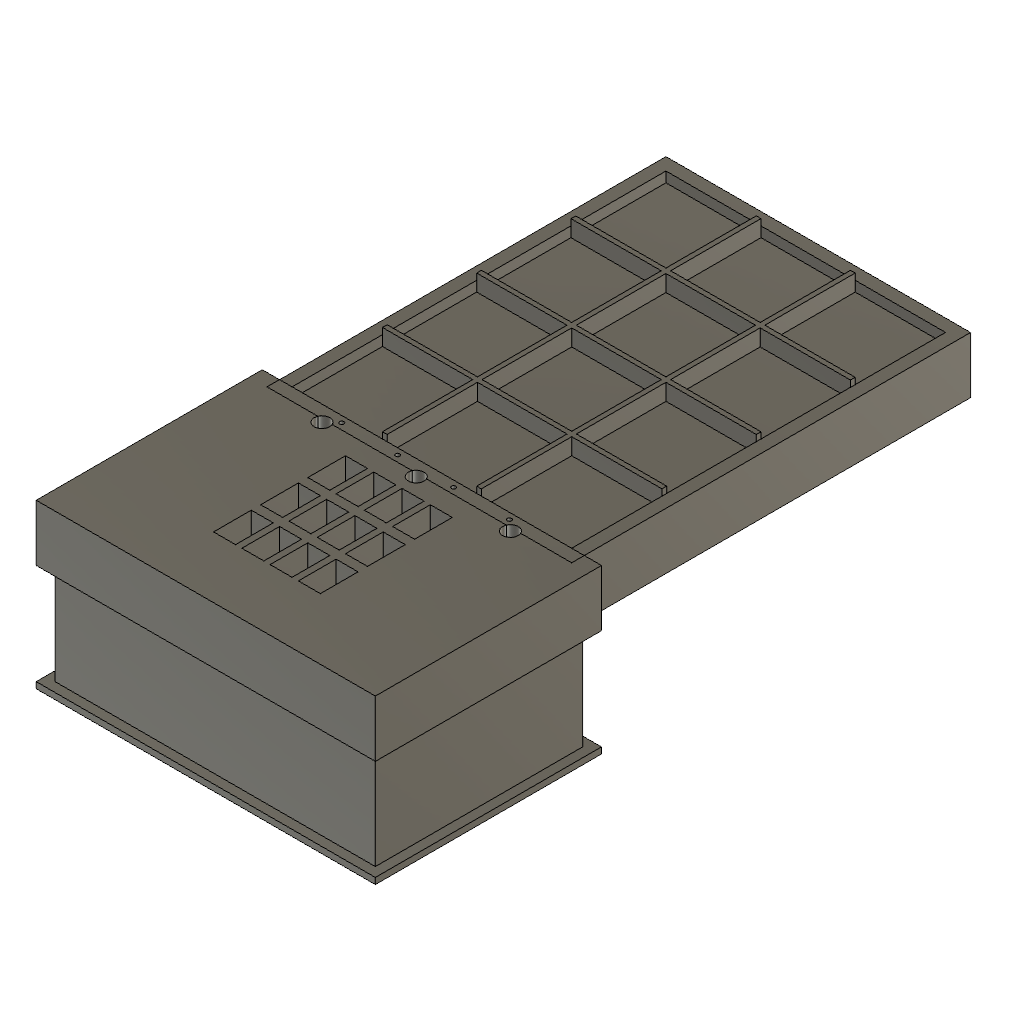
BedPrototype_before (Autodesk Fusion 360 design; units mm, degrees)
part number: 2026-11-06-12-43-00-415
Autodesk Fusion 360 part; units mm, degrees
sketch "BedFrame_CellDeckSketch" plane through (0, 0, 0) normal (0, 0, 1) x (1, 0, 0)
  line L0 (-97, -127) -> (97, -127)
  line L1 (97, -127) -> (97, 127)
  line L2 (97, 127) -> (-97, 127)
  line L3 (-97, 127) -> (-97, -127)
extrude "BedFrame_CellDeckExtrude" add sketch "BedFrame_CellDeckSketch" along normal blind 36 makes body 1
ref_plane "WorkPlane50" through (0, 0, 36) normal (0, 0, 1) x (1, 0, 0)
ref_plane "WorkPlane51" through (0, 0, 28) normal (0, 0, 1) x (1, 0, 0)
ref_plane "WorkPlane52" through (0, 0, 4) normal (0, 0, 1) x (1, 0, 0)
sketch "BedFrame_Well_0_0" plane through (0, 0, 36) normal (0, 0, 1) x (1, 0, 0)
  line L0 (-89, -119) -> (-31, -119)
  line L1 (-31, -119) -> (-31, -61)
  line L2 (-31, -61) -> (-89, -61)
  line L3 (-89, -61) -> (-89, -119)
extrude "BedFrame_WellCut_0_0" cut sketch "BedFrame_Well_0_0" against normal blind 6.5 bodies 1
sketch "Sketch1205" plane through (0, 0, 28) normal (0, 0, 1) x (1, 0, 0)
  circle A0 centre (-60, -90) radius 3.25
extrude "BedFrame_Port_0_0" cut sketch "Sketch1205" against normal blind 4 bodies 1
sketch "Sketch1206" plane through (0, 0, 28) normal (0, 0, 1) x (1, 0, 0)
  circle A0 centre (-60, -90) radius 5
extrude "BedFrame_Stem_0_0" cut sketch "Sketch1206" against normal blind 14 bodies 1
sketch "BedFrame_Run_0_0" plane through (0, 0, 4) normal (0, 0, 1) x (1, 0, 0)
  line L0 (-65, -119) -> (-55, -119)
  line L1 (-55, -119) -> (-55, -90)
  line L2 (-55, -90) -> (-65, -90)
  line L3 (-65, -90) -> (-65, -119)
extrude "BedFrame_RunCut_0_0" cut sketch "BedFrame_Run_0_0" against normal blind 12 bodies 1
sketch "BedFrame_Clip_0_0_1" plane through (0, 0, 4) normal (0, 0, 1) x (1, 0, 0)
  line L0 (-72, -101.6667) -> (-60, -101.6667)
  line L1 (-60, -101.6667) -> (-60, -97.6667)
  line L2 (-60, -97.6667) -> (-72, -97.6667)
  line L3 (-72, -97.6667) -> (-72, -101.6667)
extrude "BedFrame_ClipSlot_0_0_1" cut sketch "BedFrame_Clip_0_0_1" against normal blind 13 bodies 1
sketch "BedFrame_Clip_0_0_2" plane through (0, 0, 4) normal (0, 0, 1) x (1, 0, 0)
  line L0 (-72, -111.3333) -> (-60, -111.3333)
  line L1 (-60, -111.3333) -> (-60, -107.3333)
  line L2 (-60, -107.3333) -> (-72, -107.3333)
  line L3 (-72, -107.3333) -> (-72, -111.3333)
extrude "BedFrame_ClipSlot_0_0_2" cut sketch "BedFrame_Clip_0_0_2" against normal blind 13 bodies 1
sketch "BedFrame_Well_0_1" plane through (0, 0, 36) normal (0, 0, 1) x (1, 0, 0)
  line L0 (-89, -59) -> (-31, -59)
  line L1 (-31, -59) -> (-31, -1)
  line L2 (-31, -1) -> (-89, -1)
  line L3 (-89, -1) -> (-89, -59)
extrude "BedFrame_WellCut_0_1" cut sketch "BedFrame_Well_0_1" against normal blind 6.5 bodies 1
sketch "Sketch1211" plane through (0, 0, 28) normal (0, 0, 1) x (1, 0, 0)
  circle A0 centre (-60, -30) radius 3.25
extrude "BedFrame_Port_0_1" cut sketch "Sketch1211" against normal blind 4 bodies 1
sketch "Sketch1212" plane through (0, 0, 28) normal (0, 0, 1) x (1, 0, 0)
  circle A0 centre (-60, -30) radius 5
extrude "BedFrame_Stem_0_1" cut sketch "Sketch1212" against normal blind 14 bodies 1
sketch "BedFrame_Run_0_1" plane through (0, 0, 4) normal (0, 0, 1) x (1, 0, 0)
  line L0 (-65, -119) -> (-55, -119)
  line L1 (-55, -119) -> (-55, -30)
  line L2 (-55, -30) -> (-65, -30)
  line L3 (-65, -30) -> (-65, -119)
extrude "BedFrame_RunCut_0_1" cut sketch "BedFrame_Run_0_1" against normal blind 12 bodies 1
sketch "BedFrame_Clip_0_1_1" plane through (0, 0, 4) normal (0, 0, 1) x (1, 0, 0)
  line L0 (-72, -61.6667) -> (-60, -61.6667)
  line L1 (-60, -61.6667) -> (-60, -57.6667)
  line L2 (-60, -57.6667) -> (-72, -57.6667)
  line L3 (-72, -57.6667) -> (-72, -61.6667)
extrude "BedFrame_ClipSlot_0_1_1" cut sketch "BedFrame_Clip_0_1_1" against normal blind 13 bodies 1
sketch "BedFrame_Clip_0_1_2" plane through (0, 0, 4) normal (0, 0, 1) x (1, 0, 0)
  line L0 (-72, -91.3333) -> (-60, -91.3333)
  line L1 (-60, -91.3333) -> (-60, -87.3333)
  line L2 (-60, -87.3333) -> (-72, -87.3333)
  line L3 (-72, -87.3333) -> (-72, -91.3333)
extrude "BedFrame_ClipSlot_0_1_2" cut sketch "BedFrame_Clip_0_1_2" against normal blind 13 bodies 1
sketch "BedFrame_Well_0_2" plane through (0, 0, 36) normal (0, 0, 1) x (1, 0, 0)
  line L0 (-89, 1) -> (-31, 1)
  line L1 (-31, 1) -> (-31, 59)
  line L2 (-31, 59) -> (-89, 59)
  line L3 (-89, 59) -> (-89, 1)
extrude "BedFrame_WellCut_0_2" cut sketch "BedFrame_Well_0_2" against normal blind 6.5 bodies 1
sketch "Sketch1217" plane through (0, 0, 28) normal (0, 0, 1) x (1, 0, 0)
  circle A0 centre (-60, 30) radius 3.25
extrude "BedFrame_Port_0_2" cut sketch "Sketch1217" against normal blind 4 bodies 1
sketch "Sketch1218" plane through (0, 0, 28) normal (0, 0, 1) x (1, 0, 0)
  circle A0 centre (-60, 30) radius 5
extrude "BedFrame_Stem_0_2" cut sketch "Sketch1218" against normal blind 14 bodies 1
sketch "BedFrame_Run_0_2" plane through (0, 0, 4) normal (0, 0, 1) x (1, 0, 0)
  line L0 (-65, -119) -> (-55, -119)
  line L1 (-55, -119) -> (-55, 30)
  line L2 (-55, 30) -> (-65, 30)
  line L3 (-65, 30) -> (-65, -119)
extrude "BedFrame_RunCut_0_2" cut sketch "BedFrame_Run_0_2" against normal blind 12 bodies 1
sketch "BedFrame_Clip_0_2_1" plane through (0, 0, 4) normal (0, 0, 1) x (1, 0, 0)
  line L0 (-72, -21.6667) -> (-60, -21.6667)
  line L1 (-60, -21.6667) -> (-60, -17.6667)
  line L2 (-60, -17.6667) -> (-72, -17.6667)
  line L3 (-72, -17.6667) -> (-72, -21.6667)
extrude "BedFrame_ClipSlot_0_2_1" cut sketch "BedFrame_Clip_0_2_1" against normal blind 13 bodies 1
sketch "BedFrame_Clip_0_2_2" plane through (0, 0, 4) normal (0, 0, 1) x (1, 0, 0)
  line L0 (-72, -71.3333) -> (-60, -71.3333)
  line L1 (-60, -71.3333) -> (-60, -67.3333)
  line L2 (-60, -67.3333) -> (-72, -67.3333)
  line L3 (-72, -67.3333) -> (-72, -71.3333)
extrude "BedFrame_ClipSlot_0_2_2" cut sketch "BedFrame_Clip_0_2_2" against normal blind 13 bodies 1
sketch "BedFrame_Well_0_3" plane through (0, 0, 36) normal (0, 0, 1) x (1, 0, 0)
  line L0 (-89, 61) -> (-31, 61)
  line L1 (-31, 61) -> (-31, 119)
  line L2 (-31, 119) -> (-89, 119)
  line L3 (-89, 119) -> (-89, 61)
extrude "BedFrame_WellCut_0_3" cut sketch "BedFrame_Well_0_3" against normal blind 6.5 bodies 1
sketch "Sketch1223" plane through (0, 0, 28) normal (0, 0, 1) x (1, 0, 0)
  circle A0 centre (-60, 90) radius 3.25
extrude "BedFrame_Port_0_3" cut sketch "Sketch1223" against normal blind 4 bodies 1
sketch "Sketch1224" plane through (0, 0, 28) normal (0, 0, 1) x (1, 0, 0)
  circle A0 centre (-60, 90) radius 5
extrude "BedFrame_Stem_0_3" cut sketch "Sketch1224" against normal blind 14 bodies 1
sketch "BedFrame_Run_0_3" plane through (0, 0, 4) normal (0, 0, 1) x (1, 0, 0)
  line L0 (-65, -119) -> (-55, -119)
  line L1 (-55, -119) -> (-55, 90)
  line L2 (-55, 90) -> (-65, 90)
  line L3 (-65, 90) -> (-65, -119)
extrude "BedFrame_RunCut_0_3" cut sketch "BedFrame_Run_0_3" against normal blind 12 bodies 1
sketch "BedFrame_Clip_0_3_1" plane through (0, 0, 4) normal (0, 0, 1) x (1, 0, 0)
  line L0 (-72, 18.3333) -> (-60, 18.3333)
  line L1 (-60, 18.3333) -> (-60, 22.3333)
  line L2 (-60, 22.3333) -> (-72, 22.3333)
  line L3 (-72, 22.3333) -> (-72, 18.3333)
extrude "BedFrame_ClipSlot_0_3_1" cut sketch "BedFrame_Clip_0_3_1" against normal blind 13 bodies 1
sketch "BedFrame_Clip_0_3_2" plane through (0, 0, 4) normal (0, 0, 1) x (1, 0, 0)
  line L0 (-72, -51.3333) -> (-60, -51.3333)
  line L1 (-60, -51.3333) -> (-60, -47.3333)
  line L2 (-60, -47.3333) -> (-72, -47.3333)
  line L3 (-72, -47.3333) -> (-72, -51.3333)
extrude "BedFrame_ClipSlot_0_3_2" cut sketch "BedFrame_Clip_0_3_2" against normal blind 13 bodies 1
sketch "BedFrame_Well_1_0" plane through (0, 0, 36) normal (0, 0, 1) x (1, 0, 0)
  line L0 (-29, -119) -> (29, -119)
  line L1 (29, -119) -> (29, -61)
  line L2 (29, -61) -> (-29, -61)
  line L3 (-29, -61) -> (-29, -119)
extrude "BedFrame_WellCut_1_0" cut sketch "BedFrame_Well_1_0" against normal blind 6.5 bodies 1
sketch "Sketch1229" plane through (0, 0, 28) normal (0, 0, 1) x (1, 0, 0)
  circle A0 centre (0, -90) radius 3.25
extrude "BedFrame_Port_1_0" cut sketch "Sketch1229" against normal blind 4 bodies 1
sketch "Sketch1230" plane through (0, 0, 28) normal (0, 0, 1) x (1, 0, 0)
  circle A0 centre (0, -90) radius 5
extrude "BedFrame_Stem_1_0" cut sketch "Sketch1230" against normal blind 14 bodies 1
sketch "BedFrame_Run_1_0" plane through (0, 0, 4) normal (0, 0, 1) x (1, 0, 0)
  line L0 (-5, -119) -> (5, -119)
  line L1 (5, -119) -> (5, -90)
  line L2 (5, -90) -> (-5, -90)
  line L3 (-5, -90) -> (-5, -119)
extrude "BedFrame_RunCut_1_0" cut sketch "BedFrame_Run_1_0" against normal blind 12 bodies 1
sketch "BedFrame_Clip_1_0_1" plane through (0, 0, 4) normal (0, 0, 1) x (1, 0, 0)
  line L0 (-12, -101.6667) -> (0, -101.6667)
  line L1 (0, -101.6667) -> (0, -97.6667)
  line L2 (0, -97.6667) -> (-12, -97.6667)
  line L3 (-12, -97.6667) -> (-12, -101.6667)
extrude "BedFrame_ClipSlot_1_0_1" cut sketch "BedFrame_Clip_1_0_1" against normal blind 13 bodies 1
sketch "BedFrame_Clip_1_0_2" plane through (0, 0, 4) normal (0, 0, 1) x (1, 0, 0)
  line L0 (-12, -111.3333) -> (0, -111.3333)
  line L1 (0, -111.3333) -> (0, -107.3333)
  line L2 (0, -107.3333) -> (-12, -107.3333)
  line L3 (-12, -107.3333) -> (-12, -111.3333)
extrude "BedFrame_ClipSlot_1_0_2" cut sketch "BedFrame_Clip_1_0_2" against normal blind 13 bodies 1
sketch "BedFrame_Well_1_1" plane through (0, 0, 36) normal (0, 0, 1) x (1, 0, 0)
  line L0 (-29, -59) -> (29, -59)
  line L1 (29, -59) -> (29, -1)
  line L2 (29, -1) -> (-29, -1)
  line L3 (-29, -1) -> (-29, -59)
extrude "BedFrame_WellCut_1_1" cut sketch "BedFrame_Well_1_1" against normal blind 6.5 bodies 1
sketch "Sketch1235" plane through (0, 0, 28) normal (0, 0, 1) x (1, 0, 0)
  circle A0 centre (0, -30) radius 3.25
extrude "BedFrame_Port_1_1" cut sketch "Sketch1235" against normal blind 4 bodies 1
sketch "Sketch1236" plane through (0, 0, 28) normal (0, 0, 1) x (1, 0, 0)
  circle A0 centre (0, -30) radius 5
extrude "BedFrame_Stem_1_1" cut sketch "Sketch1236" against normal blind 14 bodies 1
sketch "BedFrame_Run_1_1" plane through (0, 0, 4) normal (0, 0, 1) x (1, 0, 0)
  line L0 (-5, -119) -> (5, -119)
  line L1 (5, -119) -> (5, -30)
  line L2 (5, -30) -> (-5, -30)
  line L3 (-5, -30) -> (-5, -119)
extrude "BedFrame_RunCut_1_1" cut sketch "BedFrame_Run_1_1" against normal blind 12 bodies 1
sketch "BedFrame_Clip_1_1_1" plane through (0, 0, 4) normal (0, 0, 1) x (1, 0, 0)
  line L0 (-12, -61.6667) -> (0, -61.6667)
  line L1 (0, -61.6667) -> (0, -57.6667)
  line L2 (0, -57.6667) -> (-12, -57.6667)
  line L3 (-12, -57.6667) -> (-12, -61.6667)
extrude "BedFrame_ClipSlot_1_1_1" cut sketch "BedFrame_Clip_1_1_1" against normal blind 13 bodies 1
sketch "BedFrame_Clip_1_1_2" plane through (0, 0, 4) normal (0, 0, 1) x (1, 0, 0)
  line L0 (-12, -91.3333) -> (0, -91.3333)
  line L1 (0, -91.3333) -> (0, -87.3333)
  line L2 (0, -87.3333) -> (-12, -87.3333)
  line L3 (-12, -87.3333) -> (-12, -91.3333)
extrude "BedFrame_ClipSlot_1_1_2" cut sketch "BedFrame_Clip_1_1_2" against normal blind 13 bodies 1
sketch "BedFrame_Well_1_2" plane through (0, 0, 36) normal (0, 0, 1) x (1, 0, 0)
  line L0 (-29, 1) -> (29, 1)
  line L1 (29, 1) -> (29, 59)
  line L2 (29, 59) -> (-29, 59)
  line L3 (-29, 59) -> (-29, 1)
extrude "BedFrame_WellCut_1_2" cut sketch "BedFrame_Well_1_2" against normal blind 6.5 bodies 1
sketch "Sketch1241" plane through (0, 0, 28) normal (0, 0, 1) x (1, 0, 0)
  circle A0 centre (0, 30) radius 3.25
extrude "BedFrame_Port_1_2" cut sketch "Sketch1241" against normal blind 4 bodies 1
sketch "Sketch1242" plane through (0, 0, 28) normal (0, 0, 1) x (1, 0, 0)
  circle A0 centre (0, 30) radius 5
extrude "BedFrame_Stem_1_2" cut sketch "Sketch1242" against normal blind 14 bodies 1
sketch "BedFrame_Run_1_2" plane through (0, 0, 4) normal (0, 0, 1) x (1, 0, 0)
  line L0 (-5, -119) -> (5, -119)
  line L1 (5, -119) -> (5, 30)
  line L2 (5, 30) -> (-5, 30)
  line L3 (-5, 30) -> (-5, -119)
extrude "BedFrame_RunCut_1_2" cut sketch "BedFrame_Run_1_2" against normal blind 12 bodies 1
sketch "BedFrame_Clip_1_2_1" plane through (0, 0, 4) normal (0, 0, 1) x (1, 0, 0)
  line L0 (-12, -21.6667) -> (0, -21.6667)
  line L1 (0, -21.6667) -> (0, -17.6667)
  line L2 (0, -17.6667) -> (-12, -17.6667)
  line L3 (-12, -17.6667) -> (-12, -21.6667)
extrude "BedFrame_ClipSlot_1_2_1" cut sketch "BedFrame_Clip_1_2_1" against normal blind 13 bodies 1
sketch "BedFrame_Clip_1_2_2" plane through (0, 0, 4) normal (0, 0, 1) x (1, 0, 0)
  line L0 (-12, -71.3333) -> (0, -71.3333)
  line L1 (0, -71.3333) -> (0, -67.3333)
  line L2 (0, -67.3333) -> (-12, -67.3333)
  line L3 (-12, -67.3333) -> (-12, -71.3333)
extrude "BedFrame_ClipSlot_1_2_2" cut sketch "BedFrame_Clip_1_2_2" against normal blind 13 bodies 1
sketch "BedFrame_Well_1_3" plane through (0, 0, 36) normal (0, 0, 1) x (1, 0, 0)
  line L0 (-29, 61) -> (29, 61)
  line L1 (29, 61) -> (29, 119)
  line L2 (29, 119) -> (-29, 119)
  line L3 (-29, 119) -> (-29, 61)
extrude "BedFrame_WellCut_1_3" cut sketch "BedFrame_Well_1_3" against normal blind 6.5 bodies 1
sketch "Sketch1247" plane through (0, 0, 28) normal (0, 0, 1) x (1, 0, 0)
  circle A0 centre (0, 90) radius 3.25
extrude "BedFrame_Port_1_3" cut sketch "Sketch1247" against normal blind 4 bodies 1
sketch "Sketch1248" plane through (0, 0, 28) normal (0, 0, 1) x (1, 0, 0)
  circle A0 centre (0, 90) radius 5
extrude "BedFrame_Stem_1_3" cut sketch "Sketch1248" against normal blind 14 bodies 1
sketch "BedFrame_Run_1_3" plane through (0, 0, 4) normal (0, 0, 1) x (1, 0, 0)
  line L0 (-5, -119) -> (5, -119)
  line L1 (5, -119) -> (5, 90)
  line L2 (5, 90) -> (-5, 90)
  line L3 (-5, 90) -> (-5, -119)
extrude "BedFrame_RunCut_1_3" cut sketch "BedFrame_Run_1_3" against normal blind 12 bodies 1
sketch "BedFrame_Clip_1_3_1" plane through (0, 0, 4) normal (0, 0, 1) x (1, 0, 0)
  line L0 (-12, 18.3333) -> (0, 18.3333)
  line L1 (0, 18.3333) -> (0, 22.3333)
  line L2 (0, 22.3333) -> (-12, 22.3333)
  line L3 (-12, 22.3333) -> (-12, 18.3333)
extrude "BedFrame_ClipSlot_1_3_1" cut sketch "BedFrame_Clip_1_3_1" against normal blind 13 bodies 1
sketch "BedFrame_Clip_1_3_2" plane through (0, 0, 4) normal (0, 0, 1) x (1, 0, 0)
  line L0 (-12, -51.3333) -> (0, -51.3333)
  line L1 (0, -51.3333) -> (0, -47.3333)
  line L2 (0, -47.3333) -> (-12, -47.3333)
  line L3 (-12, -47.3333) -> (-12, -51.3333)
extrude "BedFrame_ClipSlot_1_3_2" cut sketch "BedFrame_Clip_1_3_2" against normal blind 13 bodies 1
sketch "BedFrame_Well_2_0" plane through (0, 0, 36) normal (0, 0, 1) x (1, 0, 0)
  line L0 (31, -119) -> (89, -119)
  line L1 (89, -119) -> (89, -61)
  line L2 (89, -61) -> (31, -61)
  line L3 (31, -61) -> (31, -119)
extrude "BedFrame_WellCut_2_0" cut sketch "BedFrame_Well_2_0" against normal blind 6.5 bodies 1
sketch "Sketch1253" plane through (0, 0, 28) normal (0, 0, 1) x (1, 0, 0)
  circle A0 centre (60, -90) radius 3.25
extrude "BedFrame_Port_2_0" cut sketch "Sketch1253" against normal blind 4 bodies 1
sketch "Sketch1254" plane through (0, 0, 28) normal (0, 0, 1) x (1, 0, 0)
  circle A0 centre (60, -90) radius 5
extrude "BedFrame_Stem_2_0" cut sketch "Sketch1254" against normal blind 14 bodies 1
sketch "BedFrame_Run_2_0" plane through (0, 0, 4) normal (0, 0, 1) x (1, 0, 0)
  line L0 (55, -119) -> (65, -119)
  line L1 (65, -119) -> (65, -90)
  line L2 (65, -90) -> (55, -90)
  line L3 (55, -90) -> (55, -119)
extrude "BedFrame_RunCut_2_0" cut sketch "BedFrame_Run_2_0" against normal blind 12 bodies 1
sketch "BedFrame_Clip_2_0_1" plane through (0, 0, 4) normal (0, 0, 1) x (1, 0, 0)
  line L0 (48, -101.6667) -> (60, -101.6667)
  line L1 (60, -101.6667) -> (60, -97.6667)
  line L2 (60, -97.6667) -> (48, -97.6667)
  line L3 (48, -97.6667) -> (48, -101.6667)
extrude "BedFrame_ClipSlot_2_0_1" cut sketch "BedFrame_Clip_2_0_1" against normal blind 13 bodies 1
sketch "BedFrame_Clip_2_0_2" plane through (0, 0, 4) normal (0, 0, 1) x (1, 0, 0)
  line L0 (48, -111.3333) -> (60, -111.3333)
  line L1 (60, -111.3333) -> (60, -107.3333)
  line L2 (60, -107.3333) -> (48, -107.3333)
  line L3 (48, -107.3333) -> (48, -111.3333)
extrude "BedFrame_ClipSlot_2_0_2" cut sketch "BedFrame_Clip_2_0_2" against normal blind 13 bodies 1
sketch "BedFrame_Well_2_1" plane through (0, 0, 36) normal (0, 0, 1) x (1, 0, 0)
  line L0 (31, -59) -> (89, -59)
  line L1 (89, -59) -> (89, -1)
  line L2 (89, -1) -> (31, -1)
  line L3 (31, -1) -> (31, -59)
extrude "BedFrame_WellCut_2_1" cut sketch "BedFrame_Well_2_1" against normal blind 6.5 bodies 1
sketch "Sketch1259" plane through (0, 0, 28) normal (0, 0, 1) x (1, 0, 0)
  circle A0 centre (60, -30) radius 3.25
extrude "BedFrame_Port_2_1" cut sketch "Sketch1259" against normal blind 4 bodies 1
sketch "Sketch1260" plane through (0, 0, 28) normal (0, 0, 1) x (1, 0, 0)
  circle A0 centre (60, -30) radius 5
extrude "BedFrame_Stem_2_1" cut sketch "Sketch1260" against normal blind 14 bodies 1
sketch "BedFrame_Run_2_1" plane through (0, 0, 4) normal (0, 0, 1) x (1, 0, 0)
  line L0 (55, -119) -> (65, -119)
  line L1 (65, -119) -> (65, -30)
  line L2 (65, -30) -> (55, -30)
  line L3 (55, -30) -> (55, -119)
extrude "BedFrame_RunCut_2_1" cut sketch "BedFrame_Run_2_1" against normal blind 12 bodies 1
sketch "BedFrame_Clip_2_1_1" plane through (0, 0, 4) normal (0, 0, 1) x (1, 0, 0)
  line L0 (48, -61.6667) -> (60, -61.6667)
  line L1 (60, -61.6667) -> (60, -57.6667)
  line L2 (60, -57.6667) -> (48, -57.6667)
  line L3 (48, -57.6667) -> (48, -61.6667)
extrude "BedFrame_ClipSlot_2_1_1" cut sketch "BedFrame_Clip_2_1_1" against normal blind 13 bodies 1
sketch "BedFrame_Clip_2_1_2" plane through (0, 0, 4) normal (0, 0, 1) x (1, 0, 0)
  line L0 (48, -91.3333) -> (60, -91.3333)
  line L1 (60, -91.3333) -> (60, -87.3333)
  line L2 (60, -87.3333) -> (48, -87.3333)
  line L3 (48, -87.3333) -> (48, -91.3333)
extrude "BedFrame_ClipSlot_2_1_2" cut sketch "BedFrame_Clip_2_1_2" against normal blind 13 bodies 1
sketch "BedFrame_Well_2_2" plane through (0, 0, 36) normal (0, 0, 1) x (1, 0, 0)
  line L0 (31, 1) -> (89, 1)
  line L1 (89, 1) -> (89, 59)
  line L2 (89, 59) -> (31, 59)
  line L3 (31, 59) -> (31, 1)
extrude "BedFrame_WellCut_2_2" cut sketch "BedFrame_Well_2_2" against normal blind 6.5 bodies 1
sketch "Sketch1265" plane through (0, 0, 28) normal (0, 0, 1) x (1, 0, 0)
  circle A0 centre (60, 30) radius 3.25
extrude "BedFrame_Port_2_2" cut sketch "Sketch1265" against normal blind 4 bodies 1
sketch "Sketch1266" plane through (0, 0, 28) normal (0, 0, 1) x (1, 0, 0)
  circle A0 centre (60, 30) radius 5
extrude "BedFrame_Stem_2_2" cut sketch "Sketch1266" against normal blind 14 bodies 1
sketch "BedFrame_Run_2_2" plane through (0, 0, 4) normal (0, 0, 1) x (1, 0, 0)
  line L0 (55, -119) -> (65, -119)
  line L1 (65, -119) -> (65, 30)
  line L2 (65, 30) -> (55, 30)
  line L3 (55, 30) -> (55, -119)
extrude "BedFrame_RunCut_2_2" cut sketch "BedFrame_Run_2_2" against normal blind 12 bodies 1
sketch "BedFrame_Clip_2_2_1" plane through (0, 0, 4) normal (0, 0, 1) x (1, 0, 0)
  line L0 (48, -21.6667) -> (60, -21.6667)
  line L1 (60, -21.6667) -> (60, -17.6667)
  line L2 (60, -17.6667) -> (48, -17.6667)
  line L3 (48, -17.6667) -> (48, -21.6667)
extrude "BedFrame_ClipSlot_2_2_1" cut sketch "BedFrame_Clip_2_2_1" against normal blind 13 bodies 1
sketch "BedFrame_Clip_2_2_2" plane through (0, 0, 4) normal (0, 0, 1) x (1, 0, 0)
  line L0 (48, -71.3333) -> (60, -71.3333)
  line L1 (60, -71.3333) -> (60, -67.3333)
  line L2 (60, -67.3333) -> (48, -67.3333)
  line L3 (48, -67.3333) -> (48, -71.3333)
extrude "BedFrame_ClipSlot_2_2_2" cut sketch "BedFrame_Clip_2_2_2" against normal blind 13 bodies 1
sketch "BedFrame_Well_2_3" plane through (0, 0, 36) normal (0, 0, 1) x (1, 0, 0)
  line L0 (31, 61) -> (89, 61)
  line L1 (89, 61) -> (89, 119)
  line L2 (89, 119) -> (31, 119)
  line L3 (31, 119) -> (31, 61)
extrude "BedFrame_WellCut_2_3" cut sketch "BedFrame_Well_2_3" against normal blind 6.5 bodies 1
sketch "Sketch1271" plane through (0, 0, 28) normal (0, 0, 1) x (1, 0, 0)
  circle A0 centre (60, 90) radius 3.25
extrude "BedFrame_Port_2_3" cut sketch "Sketch1271" against normal blind 4 bodies 1
sketch "Sketch1272" plane through (0, 0, 28) normal (0, 0, 1) x (1, 0, 0)
  circle A0 centre (60, 90) radius 5
extrude "BedFrame_Stem_2_3" cut sketch "Sketch1272" against normal blind 14 bodies 1
sketch "BedFrame_Run_2_3" plane through (0, 0, 4) normal (0, 0, 1) x (1, 0, 0)
  line L0 (55, -119) -> (65, -119)
  line L1 (65, -119) -> (65, 90)
  line L2 (65, 90) -> (55, 90)
  line L3 (55, 90) -> (55, -119)
extrude "BedFrame_RunCut_2_3" cut sketch "BedFrame_Run_2_3" against normal blind 12 bodies 1
sketch "BedFrame_Clip_2_3_1" plane through (0, 0, 4) normal (0, 0, 1) x (1, 0, 0)
  line L0 (48, 18.3333) -> (60, 18.3333)
  line L1 (60, 18.3333) -> (60, 22.3333)
  line L2 (60, 22.3333) -> (48, 22.3333)
  line L3 (48, 22.3333) -> (48, 18.3333)
extrude "BedFrame_ClipSlot_2_3_1" cut sketch "BedFrame_Clip_2_3_1" against normal blind 13 bodies 1
sketch "BedFrame_Clip_2_3_2" plane through (0, 0, 4) normal (0, 0, 1) x (1, 0, 0)
  line L0 (48, -51.3333) -> (60, -51.3333)
  line L1 (60, -51.3333) -> (60, -47.3333)
  line L2 (60, -47.3333) -> (48, -47.3333)
  line L3 (48, -47.3333) -> (48, -51.3333)
extrude "BedFrame_ClipSlot_2_3_2" cut sketch "BedFrame_Clip_2_3_2" against normal blind 13 bodies 1
ref_plane "WorkPlane53" through (0, 0, 16) normal (0, 0, 1) x (1, 0, 0)
sketch "BedFrame_RibX_0" plane through (0, 0, 16) normal (0, 0, 1) x (1, 0, 0)
  line L0 (-31.5, -119) -> (-28.5, -119)
  line L1 (-28.5, -119) -> (-28.5, 119)
  line L2 (-28.5, 119) -> (-31.5, 119)
  line L3 (-31.5, 119) -> (-31.5, -119)
extrude "BedFrame_RibX_0 (1)" add sketch "BedFrame_RibX_0" along normal blind 24 bodies 1
sketch "BedFrame_RibX_1" plane through (0, 0, 16) normal (0, 0, 1) x (1, 0, 0)
  line L0 (28.5, -119) -> (31.5, -119)
  line L1 (31.5, -119) -> (31.5, 119)
  line L2 (31.5, 119) -> (28.5, 119)
  line L3 (28.5, 119) -> (28.5, -119)
extrude "BedFrame_RibX_1 (1)" add sketch "BedFrame_RibX_1" along normal blind 24 bodies 1
sketch "BedFrame_RibY_0" plane through (0, 0, 16) normal (0, 0, 1) x (1, 0, 0)
  line L0 (-89, -61.5) -> (89, -61.5)
  line L1 (89, -61.5) -> (89, -58.5)
  line L2 (89, -58.5) -> (-89, -58.5)
  line L3 (-89, -58.5) -> (-89, -61.5)
extrude "BedFrame_RibY_0 (1)" add sketch "BedFrame_RibY_0" along normal blind 24 bodies 1
sketch "BedFrame_RibY_1" plane through (0, 0, 16) normal (0, 0, 1) x (1, 0, 0)
  line L0 (-89, -1.5) -> (89, -1.5)
  line L1 (89, -1.5) -> (89, 1.5)
  line L2 (89, 1.5) -> (-89, 1.5)
  line L3 (-89, 1.5) -> (-89, -1.5)
extrude "BedFrame_RibY_1 (1)" add sketch "BedFrame_RibY_1" along normal blind 24 bodies 1
sketch "BedFrame_RibY_2" plane through (0, 0, 16) normal (0, 0, 1) x (1, 0, 0)
  line L0 (-89, 58.5) -> (89, 58.5)
  line L1 (89, 58.5) -> (89, 61.5)
  line L2 (89, 61.5) -> (-89, 61.5)
  line L3 (-89, 61.5) -> (-89, 58.5)
extrude "BedFrame_RibY_2 (1)" add sketch "BedFrame_RibY_2" along normal blind 24 bodies 1
sketch "Sketch1281" plane through (0, 0, 36) normal (0, 0, 1) x (1, 0, 0)
  circle A0 centre (-53.4, -123) radius 1.35
extrude "BedFrame_JointScrewCell_0" cut sketch "Sketch1281" against normal blind 38 bodies 1
sketch "Sketch1282" plane through (0, 0, 36) normal (0, 0, 1) x (1, 0, 0)
  circle A0 centre (-17.8, -123) radius 1.35
extrude "BedFrame_JointScrewCell_1" cut sketch "Sketch1282" against normal blind 38 bodies 1
sketch "Sketch1283" plane through (0, 0, 36) normal (0, 0, 1) x (1, 0, 0)
  circle A0 centre (17.8, -123) radius 1.35
extrude "BedFrame_JointScrewCell_2" cut sketch "Sketch1283" against normal blind 38 bodies 1
sketch "Sketch1284" plane through (0, 0, 36) normal (0, 0, 1) x (1, 0, 0)
  circle A0 centre (53.4, -123) radius 1.35
extrude "BedFrame_JointScrewCell_3" cut sketch "Sketch1284" against normal blind 38 bodies 1
sketch "BedFrame_ServiceCapSketch" plane through (0, 0, 0) normal (0, 0, 1) x (1, 0, 0)
  line L0 (-108, -263) -> (108, -263)
  line L1 (108, -263) -> (108, -119)
  line L2 (108, -119) -> (-108, -119)
  line L3 (-108, -119) -> (-108, -263)
extrude "BedFrame_ServiceCap" add sketch "BedFrame_ServiceCapSketch" along normal blind 36 separate body makes body 2
sketch "BedFrame_Valve_0" plane through (0, 0, 36) normal (0, 0, 1) x (1, 0, 0)
  line L0 (-34, -164) -> (-20, -164)
  line L1 (-20, -164) -> (-20, -140)
  line L2 (-20, -140) -> (-34, -140)
  line L3 (-34, -140) -> (-34, -164)
extrude "BedFrame_ValvePocket_0" cut sketch "BedFrame_Valve_0" against normal blind 27 bodies 2
sketch "BedFrame_Valve_1" plane through (0, 0, 36) normal (0, 0, 1) x (1, 0, 0)
  line L0 (-16, -164) -> (-2, -164)
  line L1 (-2, -164) -> (-2, -140)
  line L2 (-2, -140) -> (-16, -140)
  line L3 (-16, -140) -> (-16, -164)
extrude "BedFrame_ValvePocket_1" cut sketch "BedFrame_Valve_1" against normal blind 27 bodies 2
sketch "BedFrame_Valve_2" plane through (0, 0, 36) normal (0, 0, 1) x (1, 0, 0)
  line L0 (2, -164) -> (16, -164)
  line L1 (16, -164) -> (16, -140)
  line L2 (16, -140) -> (2, -140)
  line L3 (2, -140) -> (2, -164)
extrude "BedFrame_ValvePocket_2" cut sketch "BedFrame_Valve_2" against normal blind 27 bodies 2
sketch "BedFrame_Valve_3" plane through (0, 0, 36) normal (0, 0, 1) x (1, 0, 0)
  line L0 (20, -164) -> (34, -164)
  line L1 (34, -164) -> (34, -140)
  line L2 (34, -140) -> (20, -140)
  line L3 (20, -140) -> (20, -164)
extrude "BedFrame_ValvePocket_3" cut sketch "BedFrame_Valve_3" against normal blind 27 bodies 2
sketch "BedFrame_Valve_4" plane through (0, 0, 36) normal (0, 0, 1) x (1, 0, 0)
  line L0 (-34, -194) -> (-20, -194)
  line L1 (-20, -194) -> (-20, -170)
  line L2 (-20, -170) -> (-34, -170)
  line L3 (-34, -170) -> (-34, -194)
extrude "BedFrame_ValvePocket_4" cut sketch "BedFrame_Valve_4" against normal blind 27 bodies 2
sketch "BedFrame_Valve_5" plane through (0, 0, 36) normal (0, 0, 1) x (1, 0, 0)
  line L0 (-16, -194) -> (-2, -194)
  line L1 (-2, -194) -> (-2, -170)
  line L2 (-2, -170) -> (-16, -170)
  line L3 (-16, -170) -> (-16, -194)
extrude "BedFrame_ValvePocket_5" cut sketch "BedFrame_Valve_5" against normal blind 27 bodies 2
sketch "BedFrame_Valve_6" plane through (0, 0, 36) normal (0, 0, 1) x (1, 0, 0)
  line L0 (2, -194) -> (16, -194)
  line L1 (16, -194) -> (16, -170)
  line L2 (16, -170) -> (2, -170)
  line L3 (2, -170) -> (2, -194)
extrude "BedFrame_ValvePocket_6" cut sketch "BedFrame_Valve_6" against normal blind 27 bodies 2
sketch "BedFrame_Valve_7" plane through (0, 0, 36) normal (0, 0, 1) x (1, 0, 0)
  line L0 (20, -194) -> (34, -194)
  line L1 (34, -194) -> (34, -170)
  line L2 (34, -170) -> (20, -170)
  line L3 (20, -170) -> (20, -194)
extrude "BedFrame_ValvePocket_7" cut sketch "BedFrame_Valve_7" against normal blind 27 bodies 2
sketch "BedFrame_Valve_8" plane through (0, 0, 36) normal (0, 0, 1) x (1, 0, 0)
  line L0 (-34, -224) -> (-20, -224)
  line L1 (-20, -224) -> (-20, -200)
  line L2 (-20, -200) -> (-34, -200)
  line L3 (-34, -200) -> (-34, -224)
extrude "BedFrame_ValvePocket_8" cut sketch "BedFrame_Valve_8" against normal blind 27 bodies 2
sketch "BedFrame_Valve_9" plane through (0, 0, 36) normal (0, 0, 1) x (1, 0, 0)
  line L0 (-16, -224) -> (-2, -224)
  line L1 (-2, -224) -> (-2, -200)
  line L2 (-2, -200) -> (-16, -200)
  line L3 (-16, -200) -> (-16, -224)
extrude "BedFrame_ValvePocket_9" cut sketch "BedFrame_Valve_9" against normal blind 27 bodies 2
sketch "BedFrame_Valve_10" plane through (0, 0, 36) normal (0, 0, 1) x (1, 0, 0)
  line L0 (2, -224) -> (16, -224)
  line L1 (16, -224) -> (16, -200)
  line L2 (16, -200) -> (2, -200)
  line L3 (2, -200) -> (2, -224)
extrude "BedFrame_ValvePocket_10" cut sketch "BedFrame_Valve_10" against normal blind 27 bodies 2
sketch "BedFrame_Valve_11" plane through (0, 0, 36) normal (0, 0, 1) x (1, 0, 0)
  line L0 (20, -224) -> (34, -224)
  line L1 (34, -224) -> (34, -200)
  line L2 (34, -200) -> (20, -200)
  line L3 (20, -200) -> (20, -224)
extrude "BedFrame_ValvePocket_11" cut sketch "BedFrame_Valve_11" against normal blind 27 bodies 2
sketch "BedFrame_ValveRun_0" plane through (0, 0, 4) normal (0, 0, 1) x (1, 0, 0)
  line L0 (-32, -160) -> (-22, -160)
  line L1 (-22, -160) -> (-22, -152)
  line L2 (-22, -152) -> (-32, -152)
  line L3 (-32, -152) -> (-32, -160)
extrude "BedFrame_ValveRunCut_0" cut sketch "BedFrame_ValveRun_0" against normal blind 12 bodies 2
sketch "BedFrame_ValveRun_1" plane through (0, 0, 4) normal (0, 0, 1) x (1, 0, 0)
  line L0 (-14, -160) -> (-4, -160)
  line L1 (-4, -160) -> (-4, -152)
  line L2 (-4, -152) -> (-14, -152)
  line L3 (-14, -152) -> (-14, -160)
extrude "BedFrame_ValveRunCut_1" cut sketch "BedFrame_ValveRun_1" against normal blind 12 bodies 2
sketch "BedFrame_ValveRun_2" plane through (0, 0, 4) normal (0, 0, 1) x (1, 0, 0)
  line L0 (4, -160) -> (14, -160)
  line L1 (14, -160) -> (14, -152)
  line L2 (14, -152) -> (4, -152)
  line L3 (4, -152) -> (4, -160)
extrude "BedFrame_ValveRunCut_2" cut sketch "BedFrame_ValveRun_2" against normal blind 12 bodies 2
sketch "BedFrame_ValveRun_3" plane through (0, 0, 4) normal (0, 0, 1) x (1, 0, 0)
  line L0 (22, -160) -> (32, -160)
  line L1 (32, -160) -> (32, -152)
  line L2 (32, -152) -> (22, -152)
  line L3 (22, -152) -> (22, -160)
extrude "BedFrame_ValveRunCut_3" cut sketch "BedFrame_ValveRun_3" against normal blind 12 bodies 2
sketch "BedFrame_ValveRun_4" plane through (0, 0, 4) normal (0, 0, 1) x (1, 0, 0)
  line L0 (-32, -190) -> (-22, -190)
  line L1 (-22, -190) -> (-22, -182)
  line L2 (-22, -182) -> (-32, -182)
  line L3 (-32, -182) -> (-32, -190)
extrude "BedFrame_ValveRunCut_4" cut sketch "BedFrame_ValveRun_4" against normal blind 12 bodies 2
sketch "BedFrame_ValveRun_5" plane through (0, 0, 4) normal (0, 0, 1) x (1, 0, 0)
  line L0 (-14, -190) -> (-4, -190)
  line L1 (-4, -190) -> (-4, -182)
  line L2 (-4, -182) -> (-14, -182)
  line L3 (-14, -182) -> (-14, -190)
extrude "BedFrame_ValveRunCut_5" cut sketch "BedFrame_ValveRun_5" against normal blind 12 bodies 2
sketch "BedFrame_ValveRun_6" plane through (0, 0, 4) normal (0, 0, 1) x (1, 0, 0)
  line L0 (4, -190) -> (14, -190)
  line L1 (14, -190) -> (14, -182)
  line L2 (14, -182) -> (4, -182)
  line L3 (4, -182) -> (4, -190)
extrude "BedFrame_ValveRunCut_6" cut sketch "BedFrame_ValveRun_6" against normal blind 12 bodies 2
sketch "BedFrame_ValveRun_7" plane through (0, 0, 4) normal (0, 0, 1) x (1, 0, 0)
  line L0 (22, -190) -> (32, -190)
  line L1 (32, -190) -> (32, -182)
  line L2 (32, -182) -> (22, -182)
  line L3 (22, -182) -> (22, -190)
extrude "BedFrame_ValveRunCut_7" cut sketch "BedFrame_ValveRun_7" against normal blind 12 bodies 2
sketch "BedFrame_ValveRun_8" plane through (0, 0, 4) normal (0, 0, 1) x (1, 0, 0)
  line L0 (-32, -220) -> (-22, -220)
  line L1 (-22, -220) -> (-22, -212)
  line L2 (-22, -212) -> (-32, -212)
  line L3 (-32, -212) -> (-32, -220)
extrude "BedFrame_ValveRunCut_8" cut sketch "BedFrame_ValveRun_8" against normal blind 12 bodies 2
sketch "BedFrame_ValveRun_9" plane through (0, 0, 4) normal (0, 0, 1) x (1, 0, 0)
  line L0 (-14, -220) -> (-4, -220)
  line L1 (-4, -220) -> (-4, -212)
  line L2 (-4, -212) -> (-14, -212)
  line L3 (-14, -212) -> (-14, -220)
extrude "BedFrame_ValveRunCut_9" cut sketch "BedFrame_ValveRun_9" against normal blind 12 bodies 2
sketch "BedFrame_ValveRun_10" plane through (0, 0, 4) normal (0, 0, 1) x (1, 0, 0)
  line L0 (4, -220) -> (14, -220)
  line L1 (14, -220) -> (14, -212)
  line L2 (14, -212) -> (4, -212)
  line L3 (4, -212) -> (4, -220)
extrude "BedFrame_ValveRunCut_10" cut sketch "BedFrame_ValveRun_10" against normal blind 12 bodies 2
sketch "BedFrame_ValveRun_11" plane through (0, 0, 4) normal (0, 0, 1) x (1, 0, 0)
  line L0 (22, -220) -> (32, -220)
  line L1 (32, -220) -> (32, -212)
  line L2 (32, -212) -> (22, -212)
  line L3 (22, -212) -> (22, -220)
extrude "BedFrame_ValveRunCut_11" cut sketch "BedFrame_ValveRun_11" against normal blind 12 bodies 2
sketch "Sketch1310" plane through (0, 0, 36) normal (0, 0, 1) x (1, 0, 0)
  circle A0 centre (-53.4, -123) radius 1.35
extrude "BedFrame_JointScrewService_0" cut sketch "Sketch1310" against normal blind 38 bodies 2
sketch "Sketch1311" plane through (0, 0, 36) normal (0, 0, 1) x (1, 0, 0)
  circle A0 centre (-17.8, -123) radius 1.35
extrude "BedFrame_JointScrewService_1" cut sketch "Sketch1311" against normal blind 38 bodies 2
sketch "Sketch1312" plane through (0, 0, 36) normal (0, 0, 1) x (1, 0, 0)
  circle A0 centre (17.8, -123) radius 1.35
extrude "BedFrame_JointScrewService_2" cut sketch "Sketch1312" against normal blind 38 bodies 2
sketch "Sketch1313" plane through (0, 0, 36) normal (0, 0, 1) x (1, 0, 0)
  circle A0 centre (53.4, -123) radius 1.35
extrude "BedFrame_JointScrewService_3" cut sketch "Sketch1313" against normal blind 38 bodies 2
ref_plane "WorkPlane54" through (0, 0, -64) normal (0, 0, 1) x (1, 0, 0)
sketch "BedFrame_EBayShellSketch" plane through (0, 0, -64) normal (0, 0, 1) x (1, 0, 0)
  line L0 (-102, -257) -> (102, -257)
  line L1 (102, -257) -> (102, -125)
  line L2 (102, -125) -> (-102, -125)
  line L3 (-102, -125) -> (-102, -257)
extrude "BedFrame_EBayShell" add sketch "BedFrame_EBayShellSketch" along normal blind 64 separate body makes body 3
sketch "BedFrame_EBayVoidSketch" plane through (0, 0, -64) normal (0, 0, 1) x (1, 0, 0)
  line L0 (-100, -255) -> (100, -255)
  line L1 (100, -255) -> (100, -127)
  line L2 (100, -127) -> (-100, -127)
  line L3 (-100, -127) -> (-100, -255)
extrude "BedFrame_EBayVoid" cut sketch "BedFrame_EBayVoidSketch" along normal blind 57 bodies 3
sketch "BedFrame_EBayFloorSketch" plane through (0, 0, -64) normal (0, 0, 1) x (1, 0, 0)
  line L0 (-100, -255) -> (100, -255)
  line L1 (100, -255) -> (100, -127)
  line L2 (100, -127) -> (-100, -127)
  line L3 (-100, -127) -> (-100, -255)
extrude "BedFrame_EBayFloor" add sketch "BedFrame_EBayFloorSketch" along normal blind 4 bodies 3
sketch "BedFrame_Pump_0" plane through (0, 0, -64) normal (0, 0, 1) x (1, 0, 0)
  line L0 (-96, -233.5) -> (-28, -233.5)
  line L1 (-28, -233.5) -> (-28, -202.5)
  line L2 (-28, -202.5) -> (-96, -202.5)
  line L3 (-96, -202.5) -> (-96, -233.5)
extrude "BedFrame_PumpPocket_0" cut sketch "BedFrame_Pump_0" along normal blind 35 bodies 3
sketch "BedFrame_Pump_1" plane through (0, 0, -64) normal (0, 0, 1) x (1, 0, 0)
  line L0 (-60, -233.5) -> (8, -233.5)
  line L1 (8, -233.5) -> (8, -202.5)
  line L2 (8, -202.5) -> (-60, -202.5)
  line L3 (-60, -202.5) -> (-60, -233.5)
extrude "BedFrame_PumpPocket_1" cut sketch "BedFrame_Pump_1" along normal blind 35 bodies 3
sketch "BedFrame_Pump_2" plane through (0, 0, -64) normal (0, 0, 1) x (1, 0, 0)
  line L0 (-24, -233.5) -> (44, -233.5)
  line L1 (44, -233.5) -> (44, -202.5)
  line L2 (44, -202.5) -> (-24, -202.5)
  line L3 (-24, -202.5) -> (-24, -233.5)
extrude "BedFrame_PumpPocket_2" cut sketch "BedFrame_Pump_2" along normal blind 35 bodies 3
sketch "BedFrame_Pump_3" plane through (0, 0, -64) normal (0, 0, 1) x (1, 0, 0)
  line L0 (12, -233.5) -> (80, -233.5)
  line L1 (80, -233.5) -> (80, -202.5)
  line L2 (80, -202.5) -> (12, -202.5)
  line L3 (12, -202.5) -> (12, -233.5)
extrude "BedFrame_PumpPocket_3" cut sketch "BedFrame_Pump_3" along normal blind 35 bodies 3
sketch "BedFrame_Pump_4" plane through (0, 0, -64) normal (0, 0, 1) x (1, 0, 0)
  line L0 (-96, -195.5) -> (-28, -195.5)
  line L1 (-28, -195.5) -> (-28, -164.5)
  line L2 (-28, -164.5) -> (-96, -164.5)
  line L3 (-96, -164.5) -> (-96, -195.5)
extrude "BedFrame_PumpPocket_4" cut sketch "BedFrame_Pump_4" along normal blind 35 bodies 3
sketch "BedFrame_Pump_5" plane through (0, 0, -64) normal (0, 0, 1) x (1, 0, 0)
  line L0 (-60, -195.5) -> (8, -195.5)
  line L1 (8, -195.5) -> (8, -164.5)
  line L2 (8, -164.5) -> (-60, -164.5)
  line L3 (-60, -164.5) -> (-60, -195.5)
extrude "BedFrame_PumpPocket_5" cut sketch "BedFrame_Pump_5" along normal blind 35 bodies 3
sketch "BedFrame_Pump_6" plane through (0, 0, -64) normal (0, 0, 1) x (1, 0, 0)
  line L0 (-24, -195.5) -> (44, -195.5)
  line L1 (44, -195.5) -> (44, -164.5)
  line L2 (44, -164.5) -> (-24, -164.5)
  line L3 (-24, -164.5) -> (-24, -195.5)
extrude "BedFrame_PumpPocket_6" cut sketch "BedFrame_Pump_6" along normal blind 35 bodies 3
sketch "BedFrame_Pump_7" plane through (0, 0, -64) normal (0, 0, 1) x (1, 0, 0)
  line L0 (12, -195.5) -> (80, -195.5)
  line L1 (80, -195.5) -> (80, -164.5)
  line L2 (80, -164.5) -> (12, -164.5)
  line L3 (12, -164.5) -> (12, -195.5)
extrude "BedFrame_PumpPocket_7" cut sketch "BedFrame_Pump_7" along normal blind 35 bodies 3
sketch "Sketch1325" plane through (0, 0, -64) normal (0, 0, 1) x (1, 0, 0)
  circle A0 centre (-92, -247) radius 2.75
extrude "BedFrame_ScrewBoss_0" add sketch "Sketch1325" along normal blind 6 bodies 3
sketch "Sketch1326" plane through (0, 0, -64) normal (0, 0, 1) x (1, 0, 0)
  circle A0 centre (-92, -247) radius 1.05
extrude "BedFrame_ScrewPilot_0" cut sketch "Sketch1326" along normal blind 12 bodies 3
sketch "Sketch1327" plane through (0, 0, -64) normal (0, 0, 1) x (1, 0, 0)
  circle A0 centre (0, -247) radius 2.75
extrude "BedFrame_ScrewBoss_1" add sketch "Sketch1327" along normal blind 6 bodies 3
sketch "Sketch1328" plane through (0, 0, -64) normal (0, 0, 1) x (1, 0, 0)
  circle A0 centre (0, -247) radius 1.05
extrude "BedFrame_ScrewPilot_1" cut sketch "Sketch1328" along normal blind 12 bodies 3
sketch "Sketch1329" plane through (0, 0, -64) normal (0, 0, 1) x (1, 0, 0)
  circle A0 centre (92, -247) radius 2.75
extrude "BedFrame_ScrewBoss_2" add sketch "Sketch1329" along normal blind 6 bodies 3
sketch "Sketch1330" plane through (0, 0, -64) normal (0, 0, 1) x (1, 0, 0)
  circle A0 centre (92, -247) radius 1.05
extrude "BedFrame_ScrewPilot_2" cut sketch "Sketch1330" along normal blind 12 bodies 3
sketch "Sketch1331" plane through (0, 0, -64) normal (0, 0, 1) x (1, 0, 0)
  circle A0 centre (-92, -191) radius 2.75
extrude "BedFrame_ScrewBoss_3" add sketch "Sketch1331" along normal blind 6 separate body makes body 4
sketch "Sketch1332" plane through (0, 0, -64) normal (0, 0, 1) x (1, 0, 0)
  circle A0 centre (-92, -191) radius 1.05
extrude "BedFrame_ScrewPilot_3" cut sketch "Sketch1332" along normal blind 12 bodies 4
sketch "Sketch1333" plane through (0, 0, -64) normal (0, 0, 1) x (1, 0, 0)
  circle A0 centre (92, -191) radius 2.75
extrude "BedFrame_ScrewBoss_4" add sketch "Sketch1333" along normal blind 6 bodies 3
sketch "Sketch1334" plane through (0, 0, -64) normal (0, 0, 1) x (1, 0, 0)
  circle A0 centre (92, -191) radius 1.05
extrude "BedFrame_ScrewPilot_4" cut sketch "Sketch1334" along normal blind 12 bodies 3
sketch "Sketch1335" plane through (0, 0, -64) normal (0, 0, 1) x (1, 0, 0)
  circle A0 centre (-92, -135) radius 2.75
extrude "BedFrame_ScrewBoss_5" add sketch "Sketch1335" along normal blind 6 bodies 3
sketch "Sketch1336" plane through (0, 0, -64) normal (0, 0, 1) x (1, 0, 0)
  circle A0 centre (-92, -135) radius 1.05
extrude "BedFrame_ScrewPilot_5" cut sketch "Sketch1336" along normal blind 12 bodies 3
sketch "Sketch1337" plane through (0, 0, -64) normal (0, 0, 1) x (1, 0, 0)
  circle A0 centre (0, -135) radius 2.75
extrude "BedFrame_ScrewBoss_6" add sketch "Sketch1337" along normal blind 6 bodies 3
sketch "Sketch1338" plane through (0, 0, -64) normal (0, 0, 1) x (1, 0, 0)
  circle A0 centre (0, -135) radius 1.05
extrude "BedFrame_ScrewPilot_6" cut sketch "Sketch1338" along normal blind 12 bodies 3
sketch "Sketch1339" plane through (0, 0, -64) normal (0, 0, 1) x (1, 0, 0)
  circle A0 centre (92, -135) radius 2.75
extrude "BedFrame_ScrewBoss_7" add sketch "Sketch1339" along normal blind 6 bodies 3
sketch "Sketch1340" plane through (0, 0, -64) normal (0, 0, 1) x (1, 0, 0)
  circle A0 centre (92, -135) radius 1.05
extrude "BedFrame_ScrewPilot_7" cut sketch "Sketch1340" along normal blind 12 bodies 3
sketch "Sketch1341" plane through (0, 0, -64) normal (0, 0, 1) x (1, 0, 0)
  circle A0 centre (21, -237) radius 3
extrude "BedFrame_ArduinoStandoff" add sketch "Sketch1341" along normal blind 6 bodies 3
sketch "Sketch1342" plane through (0, 0, -64) normal (0, 0, 1) x (1, 0, 0)
  circle A0 centre (21, -237) radius 1.25
extrude "BedFrame_StandoffHole" cut sketch "Sketch1342" along normal blind 10 bodies 3
sketch "Sketch1343" plane through (0, 0, -64) normal (0, 0, 1) x (1, 0, 0)
  circle A0 centre (21, -191) radius 3
extrude "BedFrame_ArduinoStandoff (1)" add sketch "Sketch1343" along normal blind 6 separate body makes body 5
sketch "Sketch1344" plane through (0, 0, -64) normal (0, 0, 1) x (1, 0, 0)
  circle A0 centre (21, -191) radius 1.25
extrude "BedFrame_StandoffHole (1)" cut sketch "Sketch1344" along normal blind 10 bodies 5
sketch "Sketch1345" plane through (0, 0, -64) normal (0, 0, 1) x (1, 0, 0)
  circle A0 centre (82, -237) radius 3
extrude "BedFrame_ArduinoStandoff (2)" add sketch "Sketch1345" along normal blind 6 bodies 3
sketch "Sketch1346" plane through (0, 0, -64) normal (0, 0, 1) x (1, 0, 0)
  circle A0 centre (82, -237) radius 1.25
extrude "BedFrame_StandoffHole (2)" cut sketch "Sketch1346" along normal blind 10 bodies 3
sketch "Sketch1347" plane through (0, 0, -64) normal (0, 0, 1) x (1, 0, 0)
  circle A0 centre (82, -191) radius 3
extrude "BedFrame_ArduinoStandoff (3)" add sketch "Sketch1347" along normal blind 6 bodies 3
sketch "Sketch1348" plane through (0, 0, -64) normal (0, 0, 1) x (1, 0, 0)
  circle A0 centre (82, -191) radius 1.25
extrude "BedFrame_StandoffHole (3)" cut sketch "Sketch1348" along normal blind 10 bodies 3
sketch "Sketch1349" plane through (0, 0, -64) normal (0, 0, 1) x (1, 0, 0)
  circle A0 centre (-60, -129) radius 5
extrude "BedFrame_TubePassThrough" cut sketch "Sketch1349" along normal blind 102 bodies 1 2 3
sketch "Sketch1350" plane through (0, 0, -64) normal (0, 0, 1) x (1, 0, 0)
  circle A0 centre (0, -129) radius 5
extrude "BedFrame_TubePassThrough (1)" cut sketch "Sketch1350" along normal blind 102 bodies 1 2 3
sketch "Sketch1351" plane through (0, 0, -64) normal (0, 0, 1) x (1, 0, 0)
  circle A0 centre (60, -129) radius 5
extrude "BedFrame_TubePassThrough (2)" cut sketch "Sketch1351" along normal blind 102 bodies 1 2 3
ref_plane "WorkPlane55" through (0, 0, -68) normal (0, 0, 1) x (1, 0, 0)
sketch "BedFrame_BottomPanelSketch" plane through (0, 0, -68) normal (0, 0, 1) x (1, 0, 0)
  line L0 (-108, -263) -> (108, -263)
  line L1 (108, -263) -> (108, -119)
  line L2 (108, -119) -> (-108, -119)
  line L3 (-108, -119) -> (-108, -263)
extrude "BedFrame_BottomPanelExtrude" add sketch "BedFrame_BottomPanelSketch" along normal blind 4 separate body makes body 6
sketch "Sketch1353" plane through (0, 0, -68) normal (0, 0, 1) x (1, 0, 0)
  circle A0 centre (-90, -245) radius 2.75
extrude "BedFrame_PanelBoss_0" add sketch "Sketch1353" along normal blind 6 bodies 3 6
sketch "Sketch1354" plane through (0, 0, -68) normal (0, 0, 1) x (1, 0, 0)
  circle A0 centre (-90, -245) radius 1.35
extrude "BedFrame_PanelScrew_0" cut sketch "Sketch1354" along normal blind 12 bodies 3
sketch "Sketch1355" plane through (0, 0, -68) normal (0, 0, 1) x (1, 0, 0)
  circle A0 centre (0, -245) radius 2.75
extrude "BedFrame_PanelBoss_1" add sketch "Sketch1355" along normal blind 6 bodies 3
sketch "Sketch1356" plane through (0, 0, -68) normal (0, 0, 1) x (1, 0, 0)
  circle A0 centre (0, -245) radius 1.35
extrude "BedFrame_PanelScrew_1" cut sketch "Sketch1356" along normal blind 12 bodies 3
sketch "Sketch1357" plane through (0, 0, -68) normal (0, 0, 1) x (1, 0, 0)
  circle A0 centre (90, -245) radius 2.75
extrude "BedFrame_PanelBoss_2" add sketch "Sketch1357" along normal blind 6 bodies 3
sketch "Sketch1358" plane through (0, 0, -68) normal (0, 0, 1) x (1, 0, 0)
  circle A0 centre (90, -245) radius 1.35
extrude "BedFrame_PanelScrew_2" cut sketch "Sketch1358" along normal blind 12 bodies 3
sketch "Sketch1359" plane through (0, 0, -68) normal (0, 0, 1) x (1, 0, 0)
  circle A0 centre (-90, -191) radius 2.75
extrude "BedFrame_PanelBoss_3" add sketch "Sketch1359" along normal blind 6 bodies 3 4
sketch "Sketch1360" plane through (0, 0, -68) normal (0, 0, 1) x (1, 0, 0)
  circle A0 centre (-90, -191) radius 1.35
extrude "BedFrame_PanelScrew_3" cut sketch "Sketch1360" along normal blind 12 bodies 3
sketch "Sketch1361" plane through (0, 0, -68) normal (0, 0, 1) x (1, 0, 0)
  circle A0 centre (90, -191) radius 2.75
extrude "BedFrame_PanelBoss_4" add sketch "Sketch1361" along normal blind 6 bodies 3
sketch "Sketch1362" plane through (0, 0, -68) normal (0, 0, 1) x (1, 0, 0)
  circle A0 centre (90, -191) radius 1.35
extrude "BedFrame_PanelScrew_4" cut sketch "Sketch1362" along normal blind 12 bodies 3
sketch "Sketch1363" plane through (0, 0, -68) normal (0, 0, 1) x (1, 0, 0)
  circle A0 centre (-90, -137) radius 2.75
extrude "BedFrame_PanelBoss_5" add sketch "Sketch1363" along normal blind 6 bodies 3
sketch "Sketch1364" plane through (0, 0, -68) normal (0, 0, 1) x (1, 0, 0)
  circle A0 centre (-90, -137) radius 1.35
extrude "BedFrame_PanelScrew_5" cut sketch "Sketch1364" along normal blind 12 bodies 3
sketch "Sketch1365" plane through (0, 0, -68) normal (0, 0, 1) x (1, 0, 0)
  circle A0 centre (0, -137) radius 2.75
extrude "BedFrame_PanelBoss_6" add sketch "Sketch1365" along normal blind 6 bodies 3
sketch "Sketch1366" plane through (0, 0, -68) normal (0, 0, 1) x (1, 0, 0)
  circle A0 centre (0, -137) radius 1.35
extrude "BedFrame_PanelScrew_6" cut sketch "Sketch1366" along normal blind 12 bodies 3
sketch "Sketch1367" plane through (0, 0, -68) normal (0, 0, 1) x (1, 0, 0)
  circle A0 centre (90, -137) radius 2.75
extrude "BedFrame_PanelBoss_7" add sketch "Sketch1367" along normal blind 6 bodies 3
sketch "Sketch1368" plane through (0, 0, -68) normal (0, 0, 1) x (1, 0, 0)
  circle A0 centre (90, -137) radius 1.35
extrude "BedFrame_PanelScrew_7" cut sketch "Sketch1368" along normal blind 12 bodies 3
equation "e_bay_x = 20" comment "Electronics bay length"
equation "e_bay_y = 12.800000000000001" comment "Electronics bay width"
equation "pump_axis_l = 6.7999999999999998" comment "370 pump axis length"
equation "pump_head_d = 3.1000000000000001" comment "Pump head diameter"
equation "pump_count = 0.80000000000000004" comment "Pump count target"
named bodies: "BedFrame_CellDeck", "BedFrame_ServiceDeck", "BedFrame_ElectronicsBay", "BedFrame_BottomPanel"
